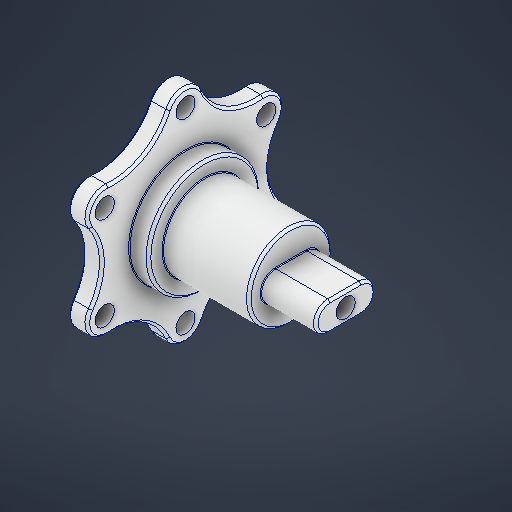
# Autodesk Inventor part: Spindle_CV_Flange_V2
Saved by Autodesk Inventor 2027.1 (Build 311270010, 270A)
## iProperties
Created: 2026-09-11
Part Number: Spindle_CV_Flange_V2
Material: Aluminum 6061
Document SubType Name: Modeling
Designer: share
Density: 2.7 g/cm^3
Appearance: Aluminum - Flat
Mass: 183.395 g
Surface Area: 204.869 cm^2
Volume: 67.924 cm^3
Author: share
Autodesk Inventor part; units mm, degrees
ref_plane "XZ Plane" through (0, 0, 0) normal (0, 1, 0) x (-1, 0, 0)
ref_plane "XY Plane" through (0, 0, 0) normal (0, 0, 1) x (1, 0, 0)
sketch "Sketch2" plane through (0, 0, 0) normal (1, 0, 0) x (0, 1, 0)
  circle A0 centre (0, 0) radius 47
  circle A1 centre (0, 0) radius 39 construction
  line L0 (0, 0) -> (39, 0) construction
  dimension "d4" = 78
  dimension "d3" = 94
  constraints: 3 coincident, 2 end point, 1 centre point, 1 horizontal, 1 horizontal alignment, 2 other
  measures "d3" diameter of A0
extrude "Flange Main Body" add sketch "Sketch2" along normal blind 8
hole "CV Interface Holes" at (0, 39, 0) direction (1, 0, 0) diameter 8 end through all
pattern_circular "CV Bolt Pattern" count 6 over 360 about axis through (-10, 0, 0) along (1, 0, 0) of "CV Interface Holes"
ref_plane "Axle Plane" through (8, 0, 0) normal (1, 0, 0) x (0, 1, 0)
sketch "Sketch3" plane through (8, 0, 0) normal (1, 0, 0) x (0, 0, -1)
  circle A0 centre (0, 0) radius 23.5
  dimension "d18" = 47
  constraints: 1 centre point, 1 coincident
  measures "d18" diameter of A0
extrude "Bearing Ring Seat" add sketch "Sketch3" along normal blind 8
sketch "Sketch4" plane through (16, 0, 0) normal (1, 0, 0) x (0, 0, -1)
  circle A0 centre (0, 0) radius 17.5
  dimension "d21" = 35
  constraints: 1 centre point, 1 coincident
  measures "d21" diameter of A0
extrude "Axle" add sketch "Sketch4" along normal blind 59
sketch "Sketch5" plane through (0, 0, 0) normal (-1, 0, 0) x (0, 0, 1)
  point P0 (0, 0)
  point P1 (0, 0)
  constraints: 1 coincident
hole "Axle Bolt Hole" at (0, 0, 0) direction (1, 0, 0) diameter 8 end through all
sketch "Sketch6" plane through (0, 0, 0) normal (-1, 0, 0) x (0, 0, 1)
  circle A0 centre (0, 0) radius 30
  circle A1 centre (0, 0) radius 4 projected
  dimension "d32" = 60
  constraints: 1 centre point, 1 coincident
  measures "d32" diameter of A0
extrude "Axle Bolt Heat Seat" cut sketch "Sketch6" against normal blind 4
sketch "Sketch7" plane through (0, 0, 0) normal (-1, 0, 0) x (0, 0, 1)
  circle A0 centre (0, 0) radius 30 projected
  circle A1 centre (-33.775, 19.5) radius 4 projected
  circle A2 centre (-33.775, -19.5) radius 4 projected
  circle A3 centre (0, -39) radius 4 projected
  circle A4 centre (33.775, -19.5) radius 4 projected
  circle A5 centre (33.775, 19.5) radius 4 projected
  circle A6 centre (0, 39) radius 4 projected
  circle A7 centre (0, 0) radius 47 projected
  line L0 (-81.4, 0) -> (68.4, 0) construction
  line L1 (0, 65.8) -> (0, -65.8) construction
  arc A8 (-43.2, -18.5138) -> (-43.2, 18.5138) centre (-60, 0) ccw
  dimension "d35" = 25
  dimension "d36" = 60
  constraints: 4 point on circle, 1 centre point, 1 point on line
  measures "d35" radius of A8
  measures "d36" distance from line of L1 A8.centre
extrude "CV Flange Weight Reduction" cut sketch "Sketch7" against normal up to surface (8 mm away) contours A8 A7 picked at (-42.7391, 4.1403)
pattern_circular "CV Flange WR Pattern" count 6 over 360 about axis through (-10, 0, 0) along (1, 0, 0) of "CV Flange Weight Reduction"
fillet "CV Flange WR Fillet" radius 8 12 edges at (4, 18.5138, -43.2) (4, 28.1554, -37.6334) (4, -18.5138, -43.2) (4, -28.1554, -37.6334) (4, -46.6692, -5.5666) (4, -46.6692, 5.5666) (4, -28.1554, 37.6334) (4, -18.5138, 43.2) (4, 18.5138, 43.2) (4, 28.1554, 37.6334) (4, 46.6692, 5.5666) (4, 46.6692, -5.5666)
sketch "Sketch8" plane through (75, 0, 0) normal (1, 0, 0) x (0, 0, -1)
  circle A0 centre (0, 0) radius 4 projected
  circle A1 centre (0, 0) radius 17.5 projected
  line L0 (-65.8, 0) -> (65.8, 0) construction
  line L1 (0, -65.8) -> (0, 65.8) construction
  line L2 (-12.5, 6) -> (12.5, 6)
  line L3 (12.5, 6) -> (12.5, -6)
  line L4 (12.5, -6) -> (-12.5, -6)
  line L5 (-12.5, -6) -> (-12.5, 6)
  dimension "d48" = 25
  dimension "d49" = 12
  constraints: 8 end point, 2 parallel, 1 horizontal, 1 perpendicular, 2 other
  measures "d48" distance between parallel lines of L3 L5
  measures "d49" distance between parallel lines of L4 L2
extrude "Wheel Hub Rectangle" cut sketch "Sketch8" against normal blind 23 contours A1
fillet "WHR Fillet" radius 6 4 edges at (63.5, 6, 12.5) (63.5, -6, 12.5) (63.5, -6, -12.5) (63.5, 6, -12.5)
chamfer "Chamfer1" distance 1 angle 45 36 edges at (16, 0, 23.5) (52, 0, 17.5) (8, 0, 35) (8, -23.1069, 40.0223) (8, -30.3109, 17.5) (8, -46.2138, 0) (8, -30.3109, -17.5) (8, -23.1069, -40.0223) (8, 0, -35) (8, 23.1069, -40.0223) (8, 30.3109, -17.5) (8, 46.2138, 0) (8, 30.3109, 17.5) (8, 23.1069, 40.0223) (0, 0, 35) (0, 23.1069, 40.0223) (0, 30.3109, 17.5) (0, 46.2138, 0) (0, 30.3109, -17.5) (0, 23.1069, -40.0223) (0, 0, -35) (0, -23.1069, -40.0223) (0, -30.3109, -17.5) (0, -46.2138, 0) (0, -30.3109, 17.5) (0, -23.1069, 40.0223) (0, 0, -30) (75, -6, 0) (75, 4.2427, -10.7427) (75, 0, -12.5) (75, -4.2427, -10.7427) (75, 6, 0) (75, 4.2427, 10.7427) (75, 0, 12.5) (75, -4.2427, 10.7427) (4, 0, -4)
fillet "Fillet3" radius 0.3 11 edges at (52, 4.2427, 10.7427) (52, 0, 12.5) (52, -4.2427, 10.7427) (52, -6, 0) (52, 4.2427, -10.7427) (52, 0, -12.5) (52, -4.2427, -10.7427) (52, 6, 0) (4, 0, -30) (8, 0, 23.5) (16, 0, 17.5)
equation "\"d6\" = Bolt_Hole_Flange_Thickness"
equation "\"Bolt_Hole_Flange_Thickness\" = 8"
body "Solid1"
